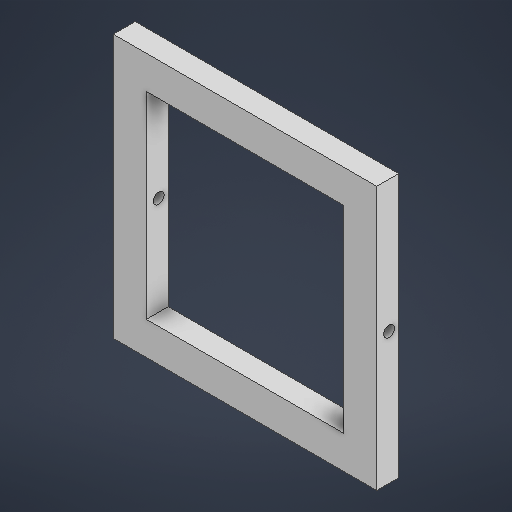
# Autodesk Inventor part: OuterFrameX_as
Saved by Autodesk Inventor 2026.2 (Build 302298010, 298A)
## iProperties
Created: 2026-03-09
Part Number: OuterFrameX_as
Material: Generic
Document SubType Name: Modeling
Designer: User
Density: 1 g/cm^3
Appearance: Default
Author: User
Autodesk Inventor part; units mm, degrees
ref_plane "YZ Plane" through (0, 0, 0) normal (1, 0, 0) x (0, 1, 0)
ref_plane "XZ Plane" through (0, 0, 0) normal (0, 1, 0) x (-1, 0, 0)
ref_plane "XY Plane" through (0, 0, 0) normal (0, 0, 1) x (1, 0, 0)
sketch "Sketch1" plane through (0, 0, 0) normal (0, 0, 1) x (1, 0, 0)
  line L0 (-52.7199, 37.3104) -> (67.2801, 37.3104)
  line L1 (67.2801, 37.3104) -> (67.2801, -82.6896)
  line L2 (67.2801, -82.6896) -> (-52.7199, -82.6896)
  line L3 (-52.7199, -82.6896) -> (-52.7199, 37.3104)
  line L4 (-37.6859, 22.2764) -> (52.246, 22.2764)
  line L5 (52.246, 22.2764) -> (52.246, -67.6555)
  line L6 (52.246, -67.6555) -> (-37.6859, -67.6555)
  line L7 (-37.6859, -67.6555) -> (-37.6859, 22.2764)
  point P0 (0, 0)
  dimension "d0" = 120
  dimension "d1" = 120
  constraints: 16 end point, 4 parallel, 2 perpendicular, 1 horizontal, 3 other
  measures "d0" distance of L0.start L0.end
  measures "d1" distance of L2.end L0.start
extrude "Extrusion1" add sketch "Sketch1" along normal blind 10
sketch "Sketch5" plane through (-52.7199, -82.6896, 0) normal (-1, 0, 0) x (0, 0, 1)
  circle A0 centre (4.3615, 60) radius 2.5
  line L0 (0, 120) -> (10, 120) projected
  point P0 (0, 82.6896)
  point P1 (5, 120)
  dimension "d14" = 5
  dimension "d15" = 60
  constraints: 1 centre point, 1 midpoint
  measures "d14" diameter of A0
  measures "d15" vertical distance of point (5, 120) A0.centre
extrude "Extrusion4" cut sketch "Sketch5" against normal through all
body "Solid1"
